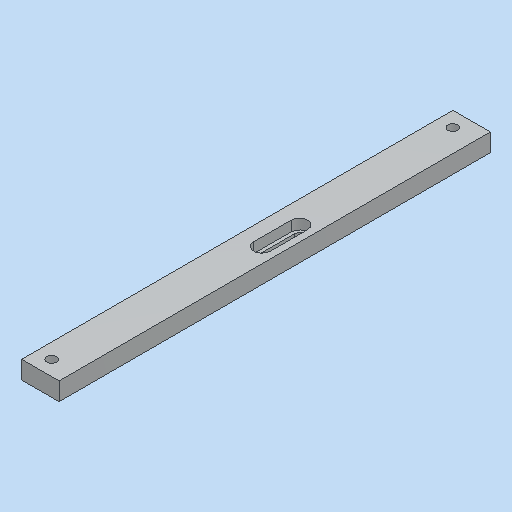
# Autodesk Inventor part: MM0948AN140_G01_120
Saved by Autodesk Inventor 2023.3 (Build 273359000, 359)
## iProperties
RuleStatus: InUse
Created: 2023-04-19
Part Number: MM0948AN140_G01_120
Material: 3.3206 AlMgSi0,5 - AW 6060
Description: =<RBPARTNOTITLE2>
Document SubType Name: Modeling
Designer: FH/Wi
Mass: 219.239 g
Surface Area: 230.052 cm^2
Volume: 81.1996 cm^3
Density: 2.7 g/cm^3
Appearance: Aluminium AnP
AnP_Kategorie: 1
AnP_Material: =<Material>
MaxAbmaße: 12 x 288 x 25 (FM)
AnP_TemplVers: 20200821
RBDOCUMENTTYPE: DRF
RBDOCUMENTVERSION: 00
RBDRAWINGMAINSCALE: 1:1
RBDRAWINGMISSINGSPEC: --
RBDRAWINGVOLUME: --
RBDSV1: 0850
RBGBEDGESIN1: +0,5
RBGBEDGESIN2: +0,2
RBGBEDGESOUT1: -0,3
RBGBEDGESOUT2: -0,1
RBMATERIAL: =<Material>
RBMATMEETS: --
RBMATNO: =<Part Number>
RBPARTMADEOF: 12 x 288 x 25 (FM)
RBPARTNO: SIEHE MNR
RBPARTNOTITLE1: manufactured part
RBPARTNOTITLE2: Anfertigungsteil
RBPARTSAFETYINDICATOR: --
RBSURFACE: anodised colourless
RBSURFACE2: eloxiert farblos
RBZEDGESNORM: ISO13715:2002-06
RBZGENDIMCLASS: m
RBZGENDIMNORM: ISO 2768-1:1989-11
RBZGENGEOCLASS: H
RBZGENGEONORM: ISO 2768-2:1989-11
RBZSURFACENORM: ISO13D2:2002-02
RBZTOLERANCENORM: ISO 14405-1:2010-12
Author: FH/Wi
Keywords: =<RBPARTMADEOF>
Comments: =<RBSURFACE2>
Revision Number: 01
Autodesk Inventor part; units mm, degrees
ref_plane "YZ Plane" through (0, 0, 0) normal (1, 0, 0) x (0, 1, 0)
ref_plane "XZ Plane" through (0, 0, 0) normal (0, 1, 0) x (-1, 0, 0)
ref_plane "XY Plane" through (0, 0, 0) normal (0, 0, 1) x (1, 0, 0)
sketch "Skizze1" plane through (0, 0, 0) normal (0, 0, 1) x (1, 0, 0)
  line L0 (-12.5, 0) -> (12.5, 0)
  line L1 (12.5, 0) -> (12.5, -288)
  line L2 (12.5, -288) -> (-12.5, -288)
  line L3 (-12.5, -288) -> (-12.5, 0)
  point P0 (0, 0)
  point P1 (0, 0)
  dimension "d0" = 25
  dimension "d1" = 288
  constraints: 8 end point, 2 parallel, 1 coincident, 1 horizontal, 1 midpoint, 1 perpendicular
  measures "d0" distance of L0.start L0.end
  measures "d1" distance of L2.end L0.start
extrude "Extrusion1" add sketch "Skizze1" along normal blind 12
sketch "Skizze2" plane through (0, 0, 0) normal (0, 0, -1) x (-1, 0, 0)
  line L0 (-12.5, 0) -> (12.5, 0) projected
  line L1 (12.5, -288) -> (-12.5, -288) projected
  line L2 (12.5, 0) -> (12.5, -288) projected
  point P0 (2.5, -10)
  point P1 (2.5, -278)
  dimension "d11" = 10
  dimension "d12" = 10
  dimension "d18" = 10
  constraints: 1 vertical alignment
  measures "d11" distance from line of point (2.5, -10) L0
  measures "d12" distance from line of L1 point (2.5, -278)
  measures "d18" distance from line of L2 point (2.5, -10)
hole "Bohrung1" at (-2.5, -10, 0) at (-2.5, -278, 0) direction (0, 0, 1) diameter 6.6 end through all counterbore diameter 11 counterbore depth 6.8 clearance for "Inbusschraube ISO 4762  versenkt" size "M6" standard "ISO"
sketch "Skizze3" plane through (0, 0, 12) normal (0, 0, 1) x (1, 0, 0)
  line L0 (2.5, -117.5) -> (2.5, -142.5) construction
  line L1 (-0.8, -117.5) -> (-0.8, -142.5)
  line L2 (5.8, -142.5) -> (5.8, -117.5)
  arc A0 (5.8, -117.5) -> (-0.8, -117.5) centre (2.5, -117.5) ccw
  arc A1 (-0.8, -142.5) -> (5.8, -142.5) centre (2.5, -142.5) ccw
  line L3 (12.5, 0) -> (-12.5, 0) projected
  line L4 (-12.5, 0) -> (-12.5, -288) projected
  point P0 (0, 0)
  point P1 (2.5, -130)
  dimension "d14" = 6.6
  dimension "d15" = 25
  dimension "d19" = 130
  dimension "d24" = 15
  constraints: 8 end point, 4 point on circle, 4 tangent, 2 centre point, 1 midpoint, 1 parallel, 1 vertical
  measures "d14" distance between parallel lines of L1 L2
  measures "d15" distance of L2.start L2.end
  measures "d19" distance from line of point (2.5, -130) L3
  measures "d24" distance from line of L0.start L4
extrude "Extrusion2" cut sketch "Skizze3" against normal through all
sketch "Skizze4" plane through (0, 0, 12) normal (0, 0, 1) x (1, 0, 0)
  line L0 (-0.8, -142.5) -> (-0.8, -117.5) projected
  arc A0 (5.8, -117.5) -> (-0.8, -117.5) centre (2.5, -117.5) ccw projected
  line L1 (5.8, -117.5) -> (5.8, -142.5) projected
  arc A1 (-0.8, -142.5) -> (5.8, -142.5) centre (2.5, -142.5) ccw projected
  line L2 (-3, -117.5) -> (-3, -142.5)
  arc A2 (-3, -142.5) -> (8, -142.5) centre (2.5, -142.5) ccw
  line L3 (8, -142.5) -> (8, -117.5)
  arc A3 (8, -117.5) -> (-3, -117.5) centre (2.5, -117.5) ccw
  point P0 (0, 0)
  point P1 (2.5, -210)
  point P2 (5.1249, -288)
  point P3 (-0.1249, -288)
  dimension "d21" = 11
  constraints: 4 end point, 4 point on circle, 2 centre point, 3 other
  measures "d21" distance between parallel lines of L3 L2
extrude "Extrusion3" cut sketch "Skizze4" against normal blind 6.8 contours L0 A0 L1 A1 | A3 L3 A2 L2
